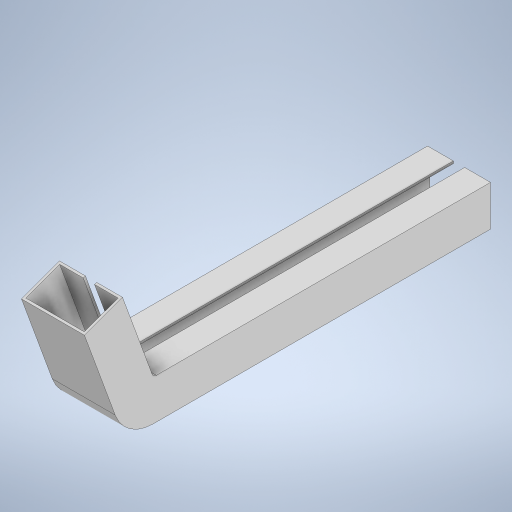
# Autodesk Inventor part: tube1
Saved by Autodesk Inventor 2024.3 (Build 283343000, 343)
## iProperties
Created: 2025-03-03
Part Number: tube1
Material: Générique
Document SubType Name: Modeling
Designer: abouabdellah
Density: 1 g/cm^3
Appearance: Par défaut
Author: abouabdellah
Autodesk Inventor part; units mm, degrees
ref_plane "YZ Plane" through (0, 0, 0) normal (1, 0, 0) x (0, 1, 0)
ref_plane "XZ Plane" through (0, 0, 0) normal (0, 1, 0) x (-1, 0, 0)
ref_plane "XY Plane" through (0, 0, 0) normal (0, 0, 1) x (1, 0, 0)
sketch "Esquisse1" plane through (0, 0, 0) normal (0, 0, 1) x (1, 0, 0)
  line L0 (-27.6316, -14.7368) -> (28.3684, -14.7368)
  line L1 (28.3684, -14.7368) -> (28.3684, 21.2632)
  line L2 (28.3684, 21.2632) -> (5.3684, 21.2632)
  line L3 (5.3684, 21.2632) -> (5.3684, 19.2632)
  line L4 (5.3684, 19.2632) -> (26.3684, 19.2632)
  line L5 (26.3684, 19.2632) -> (26.3684, -12.7368)
  line L6 (26.3684, -12.7368) -> (-25.6316, -12.7368)
  line L7 (-25.6316, -12.7368) -> (-25.6316, 19.2632)
  line L8 (-25.6316, 19.2632) -> (-4.6316, 19.2632)
  line L9 (-4.6316, 19.2632) -> (-4.6316, 21.2632)
  line L10 (-4.6316, 21.2632) -> (-27.6316, 21.2632)
  line L11 (-27.6316, 21.2632) -> (-27.6316, -14.7368)
  point P0 (0, 0)
  dimension "d0" = 2
  dimension "d1" = 2
  dimension "d2" = 2
  dimension "d3" = 2
  dimension "d4" = 52
  dimension "d5" = 32
  dimension "d6" = 10
  dimension "d7" = 23
  constraints: 24 end point, 9 perpendicular, 4 point on line, 1 horizontal
  measures "d0" distance between parallel lines of L10 L8
  measures "d1" distance between parallel lines of L1 L5
  measures "d2" distance between parallel lines of L11 L7
  measures "d3" distance between parallel lines of L6 L0
  measures "d4" distance between parallel lines of L7 L5
  measures "d5" distance between parallel lines of L6 L4
  measures "d6" distance between parallel lines of L9 L3
  measures "d7" distance between parallel lines of L11 L9
extrude "Extrusion1" add sketch "Esquisse1" against normal blind 300
sketch "Esquisse9" plane through (0, 0, 0) normal (0, 0, 1) x (1, 0, 0)
  line L0 (28.3684, -14.7368) -> (28.3684, 21.2632) projected
  line L1 (28.3684, 21.2632) -> (5.3684, 21.2632) projected
  line L2 (5.3684, 21.2632) -> (5.3684, 19.2632) projected
  line L3 (5.3684, 19.2632) -> (26.3684, 19.2632) projected
  line L4 (26.3684, 19.2632) -> (26.3684, -12.7368) projected
  line L5 (26.3684, -12.7368) -> (-25.6316, -12.7368) projected
  line L6 (-25.6316, -12.7368) -> (-25.6316, 19.2632) projected
  line L7 (-25.6316, 19.2632) -> (-4.6316, 19.2632) projected
  line L8 (-4.6316, 19.2632) -> (-4.6316, 21.2632) projected
  line L9 (-4.6316, 21.2632) -> (-27.6316, 21.2632) projected
  line L10 (-27.6316, 21.2632) -> (-27.6316, -14.7368) projected
  line L11 (-27.6316, -14.7368) -> (28.3684, -14.7368) projected
  point P0 (0, 0)
revolve "Révolution4" add sketch "Esquisse9" angle 70 about axis through (-4.6316, 21.2632, 0) along (-1, 0, 0)
sketch "Esquisse10" plane through (5.3684, 21.2632, 0) normal (0, 0.9397, 0.342) x (1, 0, 0)
  line L0 (23, 0) -> (0, 0) projected
  line L1 (0, 0) -> (0, -2) projected
  line L2 (0, -2) -> (21, -2) projected
  line L3 (21, -2) -> (21, -34) projected
  line L4 (21, -34) -> (-31, -34) projected
  line L5 (-31, -34) -> (-31, -2) projected
  line L6 (-31, -2) -> (-10, -2) projected
  line L7 (-10, -2) -> (-10, 0) projected
  line L8 (-10, 0) -> (-33, 0) projected
  line L9 (-33, 0) -> (-33, -36) projected
  line L10 (-33, -36) -> (23, -36) projected
  line L11 (23, -36) -> (23, 0) projected
  point P0 (-5.3684, -7.2724)
extrude "Extrusion4" add sketch "Esquisse10" along normal blind 80
fillet "Congé1" radius 4 2 edges at (16.8684, 21.2632, 0) (-16.1316, 21.2632, 0)
